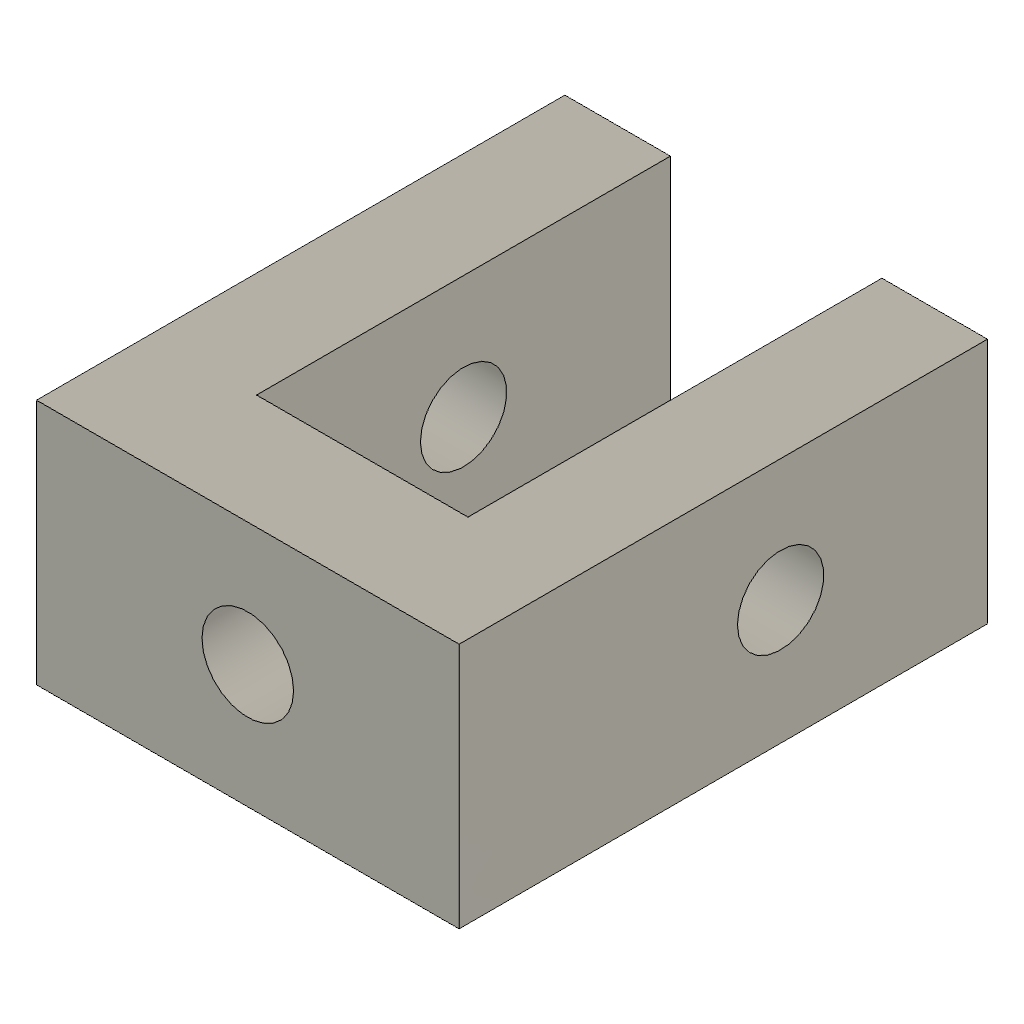
tensor_pieza_movil (Autodesk Fusion 360 design; units mm, degrees)
Autodesk Fusion 360 part; units mm, degrees
sketch "Boceto1" plane through (0, 0, 0) normal (0, 1, 0) x (1, 0, 0)
  line L0 (0, 0) -> (-79.9092, 0) construction
  line L1 (0, -34.3505) -> (0, 32.121) construction
  line L2 (0, 0) -> (-12, 0)
  line L3 (0, 0) -> (12, 0)
  line L4 (-12, 0) -> (-12, 30)
  line L5 (12, 0) -> (12, 30)
  line L6 (-12, 30) -> (-6, 30)
  line L7 (12, 30) -> (6, 30)
  line L8 (-6, 30) -> (-6, 6.5)
  line L9 (-6, 6.5) -> (6, 6.5)
  line L10 (6, 6.5) -> (6, 30)
  dimension "d1" = 12
  dimension "d2" = 12
  dimension "d3" = 30
  dimension "d4" = 6
  dimension "d5" = 6
  dimension "d6" = 23.5
  dimension "d7" = 30
  dimension "d8" = 24
  dimension "d9" = 12
  constraint coincident L0.start L2.start
  constraint horizontal L0
  constraint perpendicular L0 L1
  constraint perpendicular L1 L2
  constraint perpendicular L1 L3
  constraint perpendicular L2 L4
  constraint perpendicular L3 L5
  constraint perpendicular L4 L6
  constraint perpendicular L5 L7
  constraint perpendicular L6 L8
  constraint perpendicular L1 L9
  constraint perpendicular L7 L10
  measures "d1" distance of L0.start L2.end
  measures "d2" distance of L0.start L3.end
  measures "d3" distance of L2.end L4.end
  measures "d4" distance of L4.end L6.end
  measures "d5" distance of L5.end L7.end
  measures "d6" distance of L6.end L8.end
  measures "d7" distance of L3 L7
  measures "d8" distance of L4 L5
  measures "d9" distance of L8.end L9.end
extrude "Extruir1" add sketch "Boceto1" along normal blind 14
sketch "Boceto2" plane through (12, 0, 0) normal (1, 0, 0) x (0, 0, -1)
  line L0 (0, 0) -> (30, 0)
  line L1 (30, 0) -> (30, 14)
  line L2 (30, 14) -> (0, 14)
  line L3 (0, 14) -> (0, 0)
  line L4 (30, 0) -> (6.5, 0) construction
  line L5 (18.25, 0) -> (18.25, 18.4995) construction
  line L6 (18.25, 7.045) -> (20.7002, 7.045) construction
  circle A0 centre (18.25, 7.045) radius 2.45
  dimension "d12" = 23.5
  dimension "d13" = 11.75
  dimension "d14" = 4.9
  constraint coincident L0.end L1.start
  constraint perpendicular L1 L4
  constraint midpoint L4 L5.start
  constraint perpendicular L0 L5
  constraint coincident L5 L6.start
  constraint perpendicular L5 L6
  constraint coincident L6.start A0.centre
  measures "d12" distance of L0.end L4.end
  measures "d13" distance of L0.end L5
  measures "d14" diameter of A0
extrude "Extruir2" cut sketch "Boceto2" against normal blind 26 contours A0
sketch "Boceto3" plane through (0, 0, 0) normal (0, 0, 1) x (1, 0, 0)
  line L0 (-12, 0) -> (12, 0)
  line L1 (12, 0) -> (12, 14)
  line L2 (12, 14) -> (-12, 14)
  line L3 (-12, 14) -> (-12, 0)
  circle A0 centre (0, 7) radius 2.6
  dimension "d17" = 5.2
  measures "d17" diameter of A0
extrude "Extruir3" cut sketch "Boceto3" against normal blind 10 contours A0
